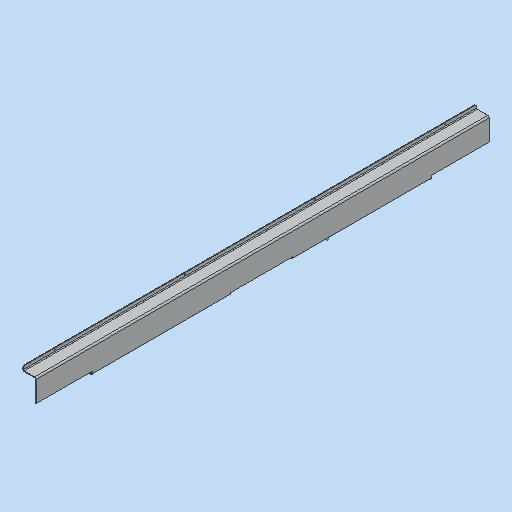
# Autodesk Inventor part: SE0004AN000_G01_101
Saved by Autodesk Inventor 2023.3 (Build 273359000, 359)
## iProperties
Part Number: SE0004AN000_G01_101
Material: 3.1645 AlCu4PbMgMn - AW 2007
Description: =<RBPARTNOTITLE2>
Document SubType Name: Blech
Designer: Benutzer
Mass: 875.626 g
Surface Area: 3135.05 cm^2
Volume: 307.237 cm^3
Density: 2.85 g/cm^3
Sheet Metal Rule: Standard_mm
Appearance: Aluminium AnP
Vendor: ASW
Flat Pattern Width: 14.3572 cm
Flat Pattern Length: 121.2 cm
Flat Pattern Area: 1740.09 cm^2
Sheet Metal Width: 143,572 mm
Sheet Metal Length: 1212,000 mm
Sheet Metal Area: 174008,876 mm^2
RBCHANGEDESCRIPTION1: Erstfreigabe
RBCHANGENO1: 00
RBDOCUMENTTYPE: DRF
RBDOCUMENTVERSION: 00
RBDRAWINGMAINSCALE: 1:1
RBDRAWINGMISSINGSPEC: --
RBDRAWINGVOLUME: --
RBDSV1: 0850
RBGBDETAILS: 43274
RBGBEDGESIN1: +0,5
RBGBEDGESIN2: +0,2
RBGBEDGESOUT1: -0,3
RBGBEDGESOUT2: -0,1
RBMATERIAL: =<Material>
RBMATMEETS: --
RBMATNO: =<Part Number>
RBORGUNITRESPONSIBLE1: AnP/TEF1
RBPARTMADEOF: 65 x 625 x 36 (FM)
RBPARTNO: SIEHE MNR
RBPARTNOTITLE1: manufactured part
RBPARTNOTITLE2: Anfertigungsteil
RBPARTSAFETYINDICATOR: --
RBSURFACE: --
RBSURFACE2: --
RBZEDGESNORM: ISO13715:2002-06
RBZGENDIMCLASS: m
RBZGENDIMNORM: ISO 2768-1:1989-11
RBZGENGEOCLASS: H
RBZGENGEONORM: ISO 2768-2:1989-11
RBZSURFACENORM: ISO13D2:2002-02
RBZTOLERANCENORM: ISO 14405-1:2010-12
AnP_Material: =<Material>
AnP_TemplVers: 20190222
AnP_Kategorie: 1
MaxAbmaße: 65 x 625 x 36 (FM)
Author: Benutzer
Keywords: =<RBPARTMADEOF>
Comments: =<RBSURFACE2>
Revision Number: 01
Autodesk Inventor part; units mm, degrees
ref_plane "XZ Plane" through (0, 0, 0) normal (0, 1, 0) x (-1, 0, 0)
ref_plane "XY Plane" through (0, 0, 0) normal (0, 0, 1) x (1, 0, 0)
sketch "Skizze1" plane through (0, 0, 0) normal (0, 0, 1) x (1, 0, 0)
  line L0 (0, 0) -> (36, 0)
  line L1 (36, 0) -> (36, 345)
  line L2 (36, 345) -> (0, 345)
  line L3 (0, 345) -> (0, 0)
  dimension "d0" = 36
  dimension "d1" = 345
  constraints: 8 end point, 2 parallel, 1 horizontal, 1 perpendicular
  measures "d0" distance of L2.end L1.end
  measures "d1" distance of L1.end L0.end
extrude "Extrusion1" add sketch "Skizze1" along normal blind 2
sketch "Skizze2" plane through (34, 345, 0) normal (1, 0, 0) x (0, 1, 0)
  line L0 (-345, 0) -> (0, 0)
  line L1 (0, 0) -> (0, 70)
  line L2 (0, 70) -> (-345, 70)
  line L3 (-345, 70) -> (-345, 0)
  constraints: 4 end point, 4 other
edge flange "Lasche1" height 70 angle 90 thickness 2 bend radius 2 thickness toward (1, 0, 0) relief tear relief width 2 relief depth 1 edges at (36, 172.5, 2) wall of the first edge with corners at (34, 0, 0) (34, 345, 0) (34, 345, 70) (34, 0, 70)
bend "Biegung1"
corner "Ecke1"
sketch "Skizze3" plane through (36, 0, 68) normal (0, 0, 1) x (-1, 0, 0)
  line L0 (0, 345) -> (0, 0)
  line L1 (0, 0) -> (36, 0)
  line L2 (36, 0) -> (36, 345)
  line L3 (36, 345) -> (0, 345)
  constraints: 4 end point, 4 other
edge flange "Lasche2" height 36 angle -90 thickness 2 bend radius 2 thickness toward (0, 0, 1) relief tear relief width 2 relief depth 1 edges at (36, 172.5, 70) wall of the first edge with corners at (36, 345, 68) (36, 0, 68) (0, 0, 68) (0, 345, 68)
bend "Biegung2"
corner "Ecke2"
sketch "Skizze4" plane through (34, 0, 4) normal (0, -1, 0) x (1, 0, 0)
  line L0 (2, 62) -> (0, 62) projected
  line L1 (0, 62) -> (0, 0) projected
  line L2 (0, 0) -> (2, 0) projected
  line L3 (2, 0) -> (2, 62) projected
  line L4 (-2, 64) -> (-2, 66) projected
  arc A0 (0, 62) -> (-2, 64) centre (-2, 62) ccw projected
  line L5 (2, 62) -> (0, 62) projected
  arc A1 (2, 62) -> (-2, 66) centre (-2, 62) ccw projected
  line L6 (-2, 64) -> (-2, 66) projected
  line L7 (-2, 66) -> (-34, 66) projected
  line L8 (-34, 66) -> (-34, 64) projected
  line L9 (-34, 64) -> (-2, 64) projected
  point P0 (-34, -4)
extrude "Extrusion2" add sketch "Skizze4" along normal blind 433.5
sketch "Skizze5" plane through (34, 345, 4) normal (0, 1, 0) x (1, 0, 0)
  line L0 (-2, -66) -> (-34, -66) projected
  line L1 (-2, -66) -> (-2, -64) projected
  line L2 (-2, -64) -> (-34, -64) projected
  line L3 (-34, -66) -> (-34, -64) projected
  line L4 (-2, -66) -> (-34, -66) projected
  arc A0 (-2, -66) -> (2, -62) centre (-2, -62) ccw projected
  arc A1 (0, -62) -> (-2, -64) centre (-2, -62) ccw projected
  line L5 (0, -62) -> (2, -62) projected
  line L6 (2, -62) -> (2, 0) projected
  line L7 (2, 0) -> (0, 0) projected
  line L8 (0, -62) -> (0, 0) projected
  point P0 (-34, 4)
extrude "Extrusion3" add sketch "Skizze5" along normal blind 433.5 contours L0 L3 L2 L1 | L5 L8 L7 L6
sketch "Skizze7" plane through (34, 345, 66) normal (0, 1, 0) x (1, 0, 0)
  line L0 (2, 62) -> (0, 62) projected
  arc A0 (2, 62) -> (-2, 66) centre (-2, 62) ccw projected
  line L1 (-2, 64) -> (-2, 66) projected
  arc A1 (0, 62) -> (-2, 64) centre (-2, 62) ccw projected
  point P0 (-34, 66)
sketch "Skizze8" plane through (34, 345, 66) normal (0, 1, 0) x (1, 0, 0)
  line L0 (2, 62) -> (0, 62) projected
  arc A0 (2, 62) -> (-2, 66) centre (-2, 62) ccw projected
  line L1 (-2, 64) -> (-2, 66) projected
  arc A1 (0, 62) -> (-2, 64) centre (-2, 62) ccw projected
  point P0 (-34, 66)
sketch "Skizze9" plane through (34, 345, 66) normal (0, 1, 0) x (1, 0, 0)
  line L0 (-2, -4) -> (-2, -2) projected
  arc A0 (-2, -4) -> (2, 0) centre (-2, 0) ccw projected
  line L1 (0, 0) -> (2, 0) projected
  arc A1 (-2, -2) -> (0, 0) centre (-2, 0) ccw projected
  point P0 (-34, 66)
extrude "Extrusion5" add sketch "Skizze9" along normal blind 583.5
sketch "Skizze11" plane through (2, -433.5, 68) normal (-1, 0, 0) x (0, -1, 0)
  line L0 (-1212, 0) -> (0, 0)
  line L1 (0, 0) -> (0, 12)
  line L2 (0, 12) -> (-1212, 12)
  line L3 (-1212, 12) -> (-1212, 0)
  constraints: 4 end point, 4 other
edge flange "Lasche3" height 12 angle 90 thickness 2 bend radius 2 thickness toward (-1, 0, 0) relief tear relief width 2 relief depth 1 edges at (0, 172.5, 70) wall of the first edge with corners at (2, 778.5, 68) (2, -433.5, 68) (2, -433.5, 80) (2, 778.5, 80)
bend "Biegung3"
corner "Ecke3"
sketch "Skizze12" plane through (34, 345, 4) normal (0, 0, -1) x (-1, 0, 0)
  line L0 (0, -345) -> (-2, -345) projected
  line L1 (-2, -345) -> (-2, -778.5) projected
  line L2 (0, -778.5) -> (-2, -778.5) projected
  line L3 (0, -345) -> (0, -778.5) projected
  line L4 (-2, 0) -> (0, 0) projected
  line L5 (0, 0) -> (0, 433.5) projected
  line L6 (-2, 433.5) -> (0, 433.5) projected
  line L7 (-2, 0) -> (-2, 433.5) projected
  point P0 (34, -345)
extrude "Extrusion7" cut sketch "Skizze12" against normal blind 3
sketch "Skizze13" plane through (0, 0, 0) normal (0, -1, 0) x (1, 0, 0)
  line L0 (32, 0) -> (32, 2) projected
  line L1 (0, 2) -> (32, 2) projected
  line L2 (0, 0) -> (0, 2) projected
  line L3 (0, 0) -> (32, 0) projected
  line L4 (34, 4) -> (36, 4) projected
  arc A0 (32, 2) -> (34, 4) centre (32, 4) ccw projected
  line L5 (32, 0) -> (32, 2) projected
  arc A1 (32, 0) -> (36, 4) centre (32, 4) ccw projected
  line L6 (36, 7) -> (36, 4) projected
  line L7 (34, 4) -> (34, 7) projected
  line L8 (34, 7) -> (36, 7) projected
extrude "Extrusion8" cut sketch "Skizze13" against normal blind 2
sketch "Skizze14" plane through (34, 345, 4) normal (0, 1, 0) x (1, 0, 0)
  line L0 (-2, 2) -> (-2, 4) projected
  line L1 (-2, 4) -> (-34, 4) projected
  line L2 (-34, 4) -> (-34, 2) projected
  line L3 (-2, 2) -> (-34, 2) projected
  line L4 (2, 0) -> (0, 0) projected
  arc A0 (2, 0) -> (-2, 4) centre (-2, 0) ccw projected
  line L5 (-2, 2) -> (-2, 4) projected
  arc A1 (0, 0) -> (-2, 2) centre (-2, 0) ccw projected
  line L6 (2, 0) -> (2, -3) projected
  line L7 (2, 0) -> (0, 0) projected
  line L8 (0, -3) -> (0, 0) projected
  line L9 (0, -3) -> (2, -3) projected
  line L10 (2, 0) -> (2, -3) projected
  line L11 (2, -3) -> (0, -3) projected
  point P0 (-34, 4)
extrude "Extrusion9" cut sketch "Skizze14" against normal blind 2
sketch "Skizze16" plane through (0, 2, 0) normal (0, -1, 0) x (1, 0, 0)
  line L0 (36, 7) -> (36, 4) projected
  line L1 (34, 7) -> (36, 7) projected
  line L2 (34, 4) -> (34, 7) projected
  arc A0 (32, 2) -> (34, 4) centre (32, 4) ccw projected
  line L3 (0, 2) -> (32, 2) projected
  line L4 (0, 0) -> (0, 2) projected
  line L5 (32, 0) -> (0, 0) projected
  arc A1 (32, 0) -> (36, 4) centre (32, 4) ccw projected
extrude "Extrusion10" add sketch "Skizze16" along normal blind 440
sketch "Skizze17" plane through (34, 343, 4) normal (0, 1, 0) x (1, 0, 0)
  line L0 (2, -3) -> (0, -3) projected
  line L1 (2, 0) -> (2, -3) projected
  arc A0 (2, 0) -> (-2, 4) centre (-2, 0) ccw projected
  line L2 (-34, 4) -> (-2, 4) projected
  line L3 (-34, 2) -> (-34, 4) projected
  line L4 (-2, 2) -> (-34, 2) projected
  arc A1 (0, 0) -> (-2, 2) centre (-2, 0) ccw projected
  line L5 (0, -3) -> (0, 0) projected
  line L6 (2, -3) -> (0, -3) projected
  line L7 (2, 0) -> (2, -3) projected
  arc A2 (2, 0) -> (-2, 4) centre (-2, 0) ccw projected
  line L8 (-34, 4) -> (-2, 4) projected
  line L9 (-34, 2) -> (-34, 4) projected
  line L10 (-2, 2) -> (-34, 2) projected
  arc A3 (0, 0) -> (-2, 2) centre (-2, 0) ccw projected
  line L11 (0, -3) -> (0, 0) projected
  line L12 (2, -3) -> (0, -3) projected
  line L13 (2, 0) -> (2, -3) projected
  arc A4 (2, 0) -> (-2, 4) centre (-2, 0) ccw projected
  line L14 (-34, 4) -> (-2, 4) projected
  line L15 (-34, 2) -> (-34, 4) projected
  line L16 (-2, 2) -> (-34, 2) projected
  arc A5 (0, 0) -> (-2, 2) centre (-2, 0) ccw projected
  line L17 (0, -3) -> (0, 0) projected
  point P0 (-34, 4)
extrude "Extrusion11" add sketch "Skizze17" along normal blind 435
sketch "Skizze18" plane through (0, 0, 0) normal (0, 0, -1) x (-1, 0, 0)
  line L0 (-32, 778) -> (-32, -438) projected
  line L1 (0, -438) -> (-32, -438) projected
  line L2 (0, 778) -> (0, -438) projected
  line L3 (-32, 778) -> (0, 778) projected
  line L4 (-32, 253) -> (0, 253)
  line L5 (0, 253) -> (0, 87)
  line L6 (0, 87) -> (-32, 87)
  line L7 (-32, 87) -> (-32, 253)
  point P0 (0, 0)
  dimension "d77" = 525
  dimension "d78" = 525
  dimension "d79" = 1216
  constraints: 8 end point, 2 parallel, 2 point on line, 1 horizontal, 1 perpendicular
  measures "d77" distance between parallel lines of L3 L4
  measures "d78" distance between parallel lines of L6 L1
  measures "d79" distance between parallel lines of L3 L1
extrude "Extrusion12" cut sketch "Skizze18" against normal blind 4 contours L4 L2 L6 L0
sketch "Skizze21" plane through (0, 0, 0) normal (0, 0, -1) x (-1, 0, 0)
  line L0 (0, 87) -> (-32, 87) projected
  line L1 (-32, 87) -> (-32, -438) projected
  line L2 (0, -438) -> (-32, -438) projected
  line L3 (0, 87) -> (0, -438) projected
  line L4 (-32, 253) -> (0, 253) projected
  line L5 (0, 778) -> (0, 253) projected
  line L6 (-32, 778) -> (0, 778) projected
  line L7 (-32, 778) -> (-32, 253) projected
  line L8 (-20.5, 344) -> (-20.5, 322) construction
  line L9 (-26, 344) -> (-26, 322)
  line L10 (-15, 322) -> (-15, 344)
  arc A0 (-15, 344) -> (-26, 344) centre (-20.5, 344) ccw
  arc A1 (-26, 322) -> (-15, 322) centre (-20.5, 322) ccw
  line L11 (-20.5, 574) -> (-20.5, 552) construction
  line L12 (-26, 574) -> (-26, 552)
  line L13 (-15, 552) -> (-15, 574)
  arc A2 (-15, 574) -> (-26, 574) centre (-20.5, 574) ccw
  arc A3 (-26, 552) -> (-15, 552) centre (-20.5, 552) ccw
  line L14 (-20.5, 18) -> (-20.5, -4) construction
  line L15 (-26, 18) -> (-26, -4)
  line L16 (-15, -4) -> (-15, 18)
  arc A4 (-15, 18) -> (-26, 18) centre (-20.5, 18) ccw
  arc A5 (-26, -4) -> (-15, -4) centre (-20.5, -4) ccw
  line L17 (-20.5, 18) -> (1.5, 18) construction
  line L18 (-20.5, -212) -> (-20.5, -234) construction
  line L19 (-26, -212) -> (-26, -234)
  line L20 (-15, -234) -> (-15, -212)
  arc A6 (-15, -212) -> (-26, -212) centre (-20.5, -212) ccw
  arc A7 (-26, -234) -> (-15, -234) centre (-20.5, -234) ccw
  line L21 (-36, -438) -> (-36, 778) projected
  point P0 (0, 0)
  point P1 (-20.5, 333)
  point P2 (-20.5, 563)
  point P3 (-20.5, 7)
  point P4 (-20.5, -223)
  dimension "d87" = 22
  dimension "d88" = 11
  dimension "d89" = 22
  dimension "d90" = 11
  dimension "d91" = 22
  dimension "d92" = 90
  dimension "d93" = 11
  dimension "d94" = 22
  dimension "d95" = 11
  dimension "d97" = 80
  dimension "d98" = 80
  dimension "d109" = 20.5
  dimension "d125" = 230
  dimension "d126" = 230
  constraints: 34 end point, 16 point on circle, 16 tangent, 8 centre point, 6 parallel, 5 point on line, 4 midpoint, 1 horizontal, 1 perpendicular
  measures "d87" distance of L8.start L8.end
  measures "d88" diameter of A1
  measures "d89" distance of L11.start L11.end
  measures "d90" diameter of A3
  measures "d91" distance of L14.start L14.end
  measures "d92" angle of L14 L17
  measures "d93" diameter of A5
  measures "d94" distance of L18.start L18.end
  measures "d95" diameter of A7
  measures "d97" distance from line of point (-20.5, 7) L0
  measures "d98" distance from line of point (-20.5, 333) L4
  measures "d109" distance from line of L3 point (-20.5, -223)
  measures "d125" distance of point (-20.5, 7) point (-20.5, -223)
  measures "d126" distance of point (-20.5, 333) point (-20.5, 563)
extrude "Extrusion14" cut sketch "Skizze21" against normal blind 4 contours A0 L10 A1 L9 | A2 L13 A3 L12 | A4 L16 A5 L15 | A6 L20 A7 L19
fillet "Rundung5" radius 5 3 edges at (1, -433.5, 80) (35, 778.5, 7) (1, 778.5, 80)
ref_plane "Arbeitsebene1" through (36, 0, 0) normal (1, 0, 0) x (0, 1, 0)
sketch "Skizze22" plane through (36, 0, 0) normal (1, 0, 0) x (0, 1, 0)
  arc A0 (778, 7) -> (778.5, 9.1794) centre (773.5, 9.1794) ccw projected
  line L0 (778.5, 66) -> (778.5, 9.1794) projected
  line L1 (778.5, 66) -> (-433.5, 66) projected
  line L2 (-433.5, 7) -> (-433.5, 66) projected
  line L3 (-438, 4) -> (-438, 7) projected
  line L4 (-438, 4) -> (778, 4) projected
  line L5 (778, 7) -> (778, 4) projected
  line L6 (253, 0) -> (87, 0) projected
  line L7 (87, 0) -> (243, 0)
  line L8 (243, 0) -> (243, 7)
  line L9 (243, 7) -> (87, 7)
  line L10 (87, 7) -> (87, 0)
  line L11 (-433.5, 7) -> (-438, 7) projected
  point P0 (0, 0)
  dimension "d106" = 7
  constraints: 8 end point, 2 parallel, 1 horizontal, 1 perpendicular
  measures "d106" distance between parallel lines of L9 L6
extrude "Extrusion15" cut sketch "Skizze22" against normal blind 4 contours L8 L6 L10 L4 | L4 L10 L9 L8
sketch "Skizze23" plane through (0, -433.5, 72) normal (-1, 0, 0) x (0, 0, 1)
  arc A0 (8, 1207) -> (3, 1212) centre (3, 1207) ccw projected
  line L0 (0, 1212) -> (3, 1212) projected
  line L1 (0, 1212) -> (0, 0) projected
  line L2 (3, 0) -> (0, 0) projected
  arc A1 (3, 0) -> (8, 5) centre (3, 5) ccw projected
  line L3 (8, 1207) -> (8, 5) projected
  point P0 (-72, 433.5)
  point P1 (4, 1128)
  dimension "d110" = 4
  dimension "d111" = 84
  measures "d110" distance from line of point (4, 1128) L3
  measures "d111" distance from line of point (4, 1128) L0
hole "Bohrung2" at (0, 694.5, 76) direction (1, 0, 0) diameter 3.242 depth 11.8 tip angle 118 thread size "M4x0.7" designation "M4" class "6H" standard "ISO Metric profile"
pattern_linear "Rechteckige Anordnung1" count 5 spacing 348 along (0, -1, 0) of "Bohrung2"
sketch "Skizze24" plane through (34, 928.5, 66) normal (0, 1, 0) x (1, 0, 0)
  line L0 (-2, -2) -> (-2, -4) projected
  arc A0 (-2, -4) -> (2, 0) centre (-2, 0) ccw projected
  line L1 (2, 0) -> (0, 0) projected
  arc A1 (-2, -2) -> (0, 0) centre (-2, 0) ccw projected
  point P0 (-34, 66)
extrude "Extrusion16" cut sketch "Skizze24" against normal up to surface (150 mm away)
sketch "Skizze25" plane through (0, 0, 0) normal (0, 0, -1) x (-1, 0, 0)
  line L0 (0, 87) -> (0, -438) projected
  line L1 (0, 87) -> (-32, 87) projected
  line L2 (-32, 87) -> (-32, -438) projected
  line L3 (0, -438) -> (-32, -438) projected
  arc A0 (-26, -234) -> (-15, -234) centre (-20.5, -234) ccw projected
  line L4 (-26, -234) -> (-26, -212) projected
  arc A1 (-15, -212) -> (-26, -212) centre (-20.5, -212) ccw projected
  line L5 (-15, -212) -> (-15, -234) projected
  arc A2 (-26, -4) -> (-15, -4) centre (-20.5, -4) ccw projected
  line L6 (-26, -4) -> (-26, 18) projected
  arc A3 (-15, 18) -> (-26, 18) centre (-20.5, 18) ccw projected
  line L7 (-15, 18) -> (-15, -4) projected
  line L8 (-36, -438) -> (-36, 87) projected
  arc A4 (-26, 322) -> (-15, 322) centre (-20.5, 322) ccw projected
  line L9 (-26, 322) -> (-26, 344) projected
  arc A5 (-15, 344) -> (-26, 344) centre (-20.5, 344) ccw projected
  line L10 (-15, 344) -> (-15, 322) projected
  arc A6 (-26, 552) -> (-15, 552) centre (-20.5, 552) ccw projected
  line L11 (-26, 552) -> (-26, 574) projected
  arc A7 (-15, 574) -> (-26, 574) centre (-20.5, 574) ccw projected
  line L12 (-15, 574) -> (-15, 552) projected
  line L13 (0, 778) -> (0, 253) projected
  line L14 (-32, 778) -> (0, 778) projected
  line L15 (-32, 778) -> (-32, 253) projected
  line L16 (-32, 253) -> (0, 253) projected
  line L17 (-36, 243) -> (-36, 778) projected
  line L18 (-41, 778.5) -> (5, 778.5)
  line L19 (5, 778.5) -> (5, 623)
  line L20 (5, 623) -> (-41, 623)
  line L21 (-41, 623) -> (-41, 778.5)
  line L22 (-41, -283) -> (5, -283)
  line L23 (5, -283) -> (5, -438)
  line L24 (5, -438) -> (-41, -438)
  line L25 (-41, -438) -> (-41, -283)
  line L26 (-32, 778.5) -> (-4, 778.5) projected
  point P0 (0, 0)
  point P1 (5, 700.75)
  point P2 (5, -360.5)
  point P3 (-41, 700.75)
  point P4 (-41, -360.5)
  dimension "d127" = 155
  dimension "d128" = 0
  dimension "d129" = 5
  dimension "d130" = 5
  dimension "d131" = 155
  dimension "d132" = 0
  constraints: 16 end point, 4 midpoint, 4 parallel, 2 horizontal, 2 perpendicular, 2 vertical alignment
  measures "d127" distance between parallel lines of L22 L3
  measures "d128" distance between parallel lines of L3 L24
  measures "d129" distance between parallel lines of L8 L25
  measures "d130" distance between parallel lines of L0 L23
  measures "d131" distance between parallel lines of L20 L14
  measures "d132" distance between parallel lines of L18 L26
extrude "Extrusion17" cut sketch "Skizze25" against normal blind 10 contours L22 L23 L24 L0 | L0 L3 L2 L22 | L2 L24 L8 L22 | L8 L24 L25 L22 | L14 L15 L20 L21 L18 L19 L13 | L13 L20 L15 L14
fillet "Rundung6" radius 5 2 edges at (0, 623, 1) (0, -283, 1)
fillet "Rundung7" radius 5 2 edges at (0, 253, 1) (0, 87, 1)
sketch "Skizze26" plane through (34, 243, 7) normal (0, -1, 0) x (1, 0, 0)
  line L0 (-29, -5) -> (-29, -7) projected
  line L1 (-2, -5) -> (-29, -5) projected
  arc A0 (-2, -5) -> (0, -3) centre (-2, -3) ccw projected
  line L2 (0, 3) -> (0, -3) projected
  line L3 (0, 3) -> (2, 3) projected
  line L4 (2, -3) -> (2, 3) projected
  arc A1 (-2, -7) -> (2, -3) centre (-2, -3) ccw projected
  line L5 (-29, -7) -> (-2, -7) projected
  line L6 (0, 0) -> (2, 0)
  point P0 (-34, -7)
  constraints: 2 end point, 2 midpoint
extrude "Extrusion18" cut sketch "Skizze26" against normal up to surface (10 mm away) contours L1 A0 L2 L6 L4 A1 L5 L0
equation "\"d4\" = BreiteBiegungsfreistellung"
equation "\"d5\" = TiefeBiegungsfreistellung"
equation "\"d6\" = MinimalRest"
equation "\"d7\" = Biegeradius"
equation "\"d10\" = Biegeradius"
equation "\"d11\" = GrößeEckenfreistellung"
equation "\"d12\" = Abstandsgröße"
equation "\"d13\" = JacobiRadiusGröße"
equation "\"d122\" = Stärke"
equation "\"d14\" = BreiteBiegungsfreistellung"
equation "\"d15\" = TiefeBiegungsfreistellung"
equation "\"d16\" = MinimalRest"
equation "\"d17\" = Biegeradius"
equation "\"d20\" = Biegeradius"
equation "\"d21\" = GrößeEckenfreistellung"
equation "\"d22\" = Abstandsgröße"
equation "\"d23\" = JacobiRadiusGröße"
equation "\"d42\" = BreiteBiegungsfreistellung"
equation "\"d43\" = TiefeBiegungsfreistellung"
equation "\"d44\" = MinimalRest"
equation "\"d45\" = Biegeradius"
equation "\"d48\" = Biegeradius"
equation "\"d49\" = GrößeEckenfreistellung"
equation "\"d50\" = Abstandsgröße"
equation "\"d51\" = JacobiRadiusGröße"
equation "\"Biegeradius\" = Stärke"
equation "\"BreiteBiegungsfreistellung\" = Stärke"
equation "\"TiefeBiegungsfreistellung\" = 0.5 * Stärke"
equation "\"GrößeEckenfreistellung\" = 4 * Stärke"
equation "\"MinimalRest\" = 2 * Stärke"
equation "\"Übergangsradius\" = Biegeradius"
equation "\"JacobiRadiusGröße\" = Biegeradius"
equation "\"Abstandsgröße\" = Stärke"
equation "\"Stärke\" = 2"
